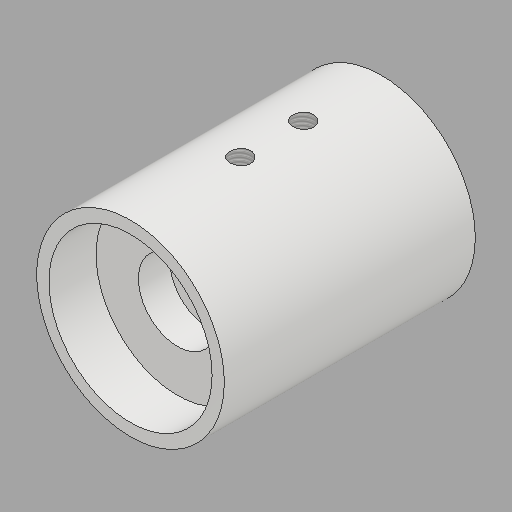
# Autodesk Inventor part: BT007_bensen22_26
Saved by Autodesk Inventor 2025.3 (Build 293356000, 356)
## iProperties
Company: HTBLA Kaindorf
RuleStatus: InUse
Created: 2026-08-10
Part Number: BT007_bensen22_26
Project: Biegeroboter
Material: ABS-Kunststoff
Description: verlängerung_aufnahme_v1
Document SubType Name: Modeling
Designer: bensen22
Density: 1.06 g/cm^3
Appearance: Glatt - Weiß
Mass: 152.119 g
Surface Area: 302.225 cm^2
Volume: 143.508 cm^3
AfterDocNew0: iProperties-Editor_aufrufen
Author: sebas
Keywords: 2026
Autodesk Inventor part; units mm, degrees
ref_plane "YZ Plane" through (0, 0, 0) normal (1, 0, 0) x (0, 1, 0)
ref_plane "XZ Plane" through (0, 0, 0) normal (0, 1, 0) x (-1, 0, 0)
sketch "Skizze3" plane through (0, 0, 0) normal (0, 0, 1) x (1, 0, 0)
  line L0 (0, -5.98) -> (0, 35.88) projected
  line L1 (-56, 0) -> (56, 0) projected
  line L2 (-40, 0) -> (-40, 29.9)
  line L3 (-40, 29.9) -> (40, 29.9)
  line L4 (40, 29.9) -> (40, 0)
  line L5 (-40, 16) -> (11, 16)
  line L6 (11, 16) -> (11, 0)
  line L7 (15, 12.5) -> (15, 0)
  line L8 (40, 26) -> (25, 26)
  line L9 (25, 26) -> (25, 12.5)
  line L10 (15, 12.5) -> (40, 12.5)
  point P0 (0, 0)
  dimension "d4" = 29.9
  dimension "d5" = 80
  dimension "d7" = 16
  dimension "d8" = 51
  dimension "d10" = 26
  dimension "d11" = 15
  dimension "d13" = 12.5
  dimension "d14" = 25
  dimension "d15" = 13.5
  constraints: 18 end point, 7 point on line, 5 perpendicular, 1 horizontal, 1 parallel, 1 vertical, 1 other
  measures "d4" distance between parallel lines of L1 L3
  measures "d5" distance between parallel lines of L4 L2
  measures "d7" distance between parallel lines of L1 L5
  measures "d8" distance between parallel lines of L2 L6
  measures "d10" distance between parallel lines of L1 L8
  measures "d11" distance between parallel lines of L4 L9
  measures "d13" distance of L7.start L7.end
  measures "d14" distance between parallel lines of L4 L7
  measures "d15" distance of L8.end L9.end
revolve "Umdrehung1" add sketch "Skizze3" angle 360 about axis through (-10, 0, 0) along (1, 0, 0) contours L5 L2 L3 L0 | L0 L3 L4 L8 L9 L10 L7 L1 L6 L5
sketch "Skizze4" plane through (0, 0, 0) normal (0, 1, 0) x (-1, 0, 0)
  line L0 (59, 5) -> (-1, 5)
  line L1 (-1, 5) -> (-1, -5)
  line L2 (-1, -5) -> (59, -5)
  line L3 (59, -5) -> (59, 5)
  line L4 (43, 0) -> (-20, 0) projected
  line L5 (0, -22.4) -> (0, 22.4) projected
  circle A0 centre (59, 0) radius 5
  circle A1 centre (-1, 0) radius 5
  line L6 (-11, 16) -> (-11, -16) projected
  point P0 (0, 0)
  point P1 (0, -4.899)
  point P2 (0, -5)
  point P3 (0, 5)
  point P4 (0, 4.899)
  dimension "d17" = 10
  dimension "d18" = 60
  dimension "d19" = 10
  dimension "d20" = 10
  dimension "d21" = 10
  constraints: 8 end point, 2 centre point, 2 midpoint, 2 parallel, 2 point on line, 1 horizontal, 1 perpendicular, 1 other
  measures "d17" distance of L2.end L0.start
  measures "d18" distance of L1.end L2.end
  measures "d19" diameter of A0
  measures "d20" diameter of A1
  measures "d21" distance from line of L1.end L6
extrude "Extrusion3" cut sketch "Skizze4" against normal blind 19 contours A0 L2 L5 A1 L0 | A0 L3 | L3 A0 | A1 L5 L4 L1 | L1 L4 A1 | A1 L4 L5 | L4 L5 A1 L1 | L1 A1 L4 | L4 A1 L5
ref_plane "Arbeitsebene4" through (0, 0, -29.9) normal (0, 0, 1) x (1, 0, 0)
sketch "Skizze5" plane through (0, 0, -29.9) normal (0, 0, 1) x (1, 0, 0)
  line L0 (-40, -29.9) -> (-40, 29.9) projected
  point P0 (0, 0)
  point P1 (-15, 0)
  point P2 (5, 0)
  dimension "d24" = 25
  dimension "d25" = 20
  measures "d24" distance from line of L0 point (-15, 0)
  measures "d25" distance of point (5, 0) point (-15, 0)
hole "Bohrung1" at (-15, 0, -29.9) at (5, 0, -29.9) direction (0, 0, 1) diameter 6.647 end through all thread size "M8x1.25" class "6H" standard "ISO Metric profile"
